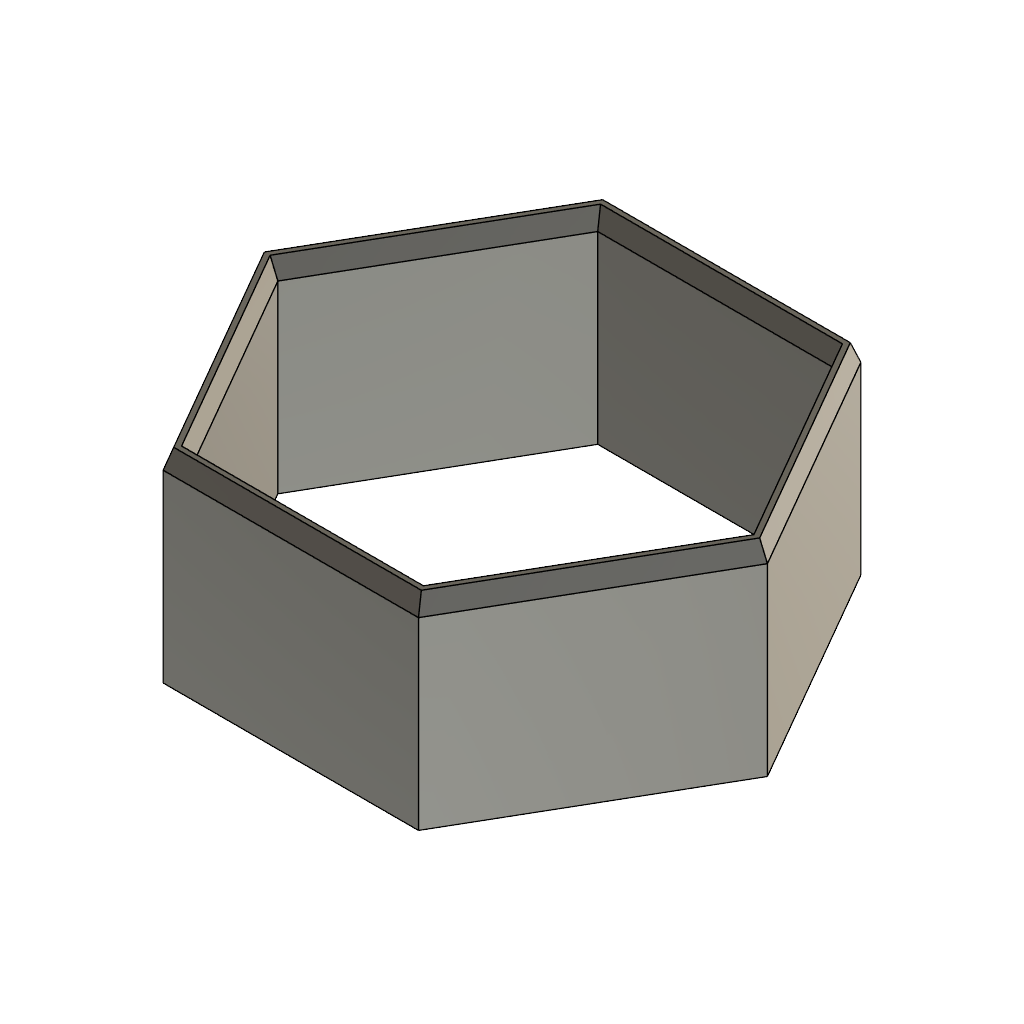
DicePopperTop (Autodesk Fusion 360 design; units mm, degrees)
Autodesk Fusion 360 part; units mm, degrees
sketch "Sketch1" plane through (0, 0, 0) normal (0, 0, 1) x (1, 0, 0)
  line L0 (-34.641, 60) -> (-69.282, 0)
  line L1 (-69.282, 0) -> (-34.641, -60)
  line L2 (-34.641, -60) -> (34.641, -60)
  line L3 (34.641, -60) -> (69.282, 0)
  line L4 (69.282, 0) -> (34.641, 60)
  line L5 (34.641, 60) -> (-34.641, 60)
  dimension "d1" = 60
  measures "d1" distance of origin L5
extrude "Extrude1" add sketch "Sketch1" along normal blind 50
sketch "Sketch2" plane through (0, 0, 50) normal (0, 0, 1) x (-1, 0, 0)
  line L0 (-34.641, -60) -> (34.641, -60)
  line L1 (34.641, -60) -> (69.282, 0)
  line L2 (69.282, 0) -> (34.641, 60)
  line L3 (34.641, 60) -> (-34.641, 60)
  line L4 (-34.641, 60) -> (-69.282, 0)
  line L5 (-69.282, 0) -> (-34.641, -60)
  line L6 (31.7543, -55) -> (63.5085, 0)
  line L7 (63.5085, 0) -> (31.7543, 55)
  line L8 (31.7543, 55) -> (-31.7543, 55)
  line L9 (-31.7543, 55) -> (-63.5085, 0)
  line L10 (-63.5085, 0) -> (-31.7543, -55)
  line L11 (-31.7543, -55) -> (31.7543, -55)
extrude "Extrude2" cut sketch "Sketch2" against normal blind 70 contours L6 L7 L8 L9 L10 L11
extrude "Extrude3" add 1 faces at (10.5848, -58.3333, 50) along direction (0, 0, 1) blind 5 draft -20
